Autodesk Fusion 360 part; units mm, degrees
(part 15 of 28)
sketch "Blinking Light House-PTH-drl_map (1)" plane through (0, 0, 1.4859) normal (0, 0, 1) x (1, 0, 0)
  line L0 (146.05, 0) -> (146.05, -5.08)
  line L1 (146.05, 0) -> (140.97, 0)
  line L2 (146.05, 0) -> (153.67, 0)
  line L3 (146.05, 0) -> (146.05, 6.985)
  line L4 (269.875, 36.83) -> (273.05, 36.83)
  line L5 (273.05, 36.83) -> (273.05, 5.08)
  line L6 (215.265, 36.83) -> (273.05, 36.83)
  line L7 (273.05, 5.08) -> (215.265, 5.08)
  line L8 (215.265, 5.08) -> (215.265, 36.83)
  line L9 (208.915, 36.83) -> (212.09, 36.83)
  line L10 (212.09, 36.83) -> (212.09, 5.08)
  line L11 (154.305, 36.83) -> (212.09, 36.83)
  line L12 (154.305, 5.08) -> (154.305, 36.83)
  line L13 (212.09, 5.08) -> (154.305, 5.08)
  line L14 (259.08, 97.79) -> (290.83, 97.79)
  line L15 (259.08, 40.005) -> (259.08, 97.79)
  line L16 (290.83, 97.79) -> (290.83, 40.005)
  line L17 (290.83, 40.005) -> (259.08, 40.005)
  line L18 (255.905, 97.79) -> (255.905, 40.005)
  line L19 (224.155, 97.79) -> (255.905, 97.79)
  line L20 (255.905, 40.005) -> (224.155, 40.005)
  line L21 (224.155, 40.005) -> (224.155, 97.79)
  line L22 (189.23, 97.79) -> (220.98, 97.79)
  line L23 (220.98, 97.79) -> (220.98, 40.005)
  line L24 (220.98, 40.005) -> (189.23, 40.005)
  line L25 (186.055, 40.005) -> (154.305, 40.005)
  line L26 (189.23, 40.005) -> (189.23, 97.79)
  line L27 (186.055, 97.79) -> (189.23, 97.79)
  line L28 (154.305, 40.005) -> (154.305, 97.79)
  line L29 (186.055, 40.005) -> (154.305, 40.005)
  line L30 (186.055, 97.79) -> (186.055, 40.005)
  line L31 (154.305, 97.79) -> (186.055, 97.79)
  line L32 (159.0815, 75.2735) -> (159.8315, 74.5235)
  line L33 (159.8315, 75.2735) -> (159.0815, 74.5235)
  line L34 (161.8515, 75.2735) -> (162.6015, 74.5235)
  line L35 (162.6015, 75.2735) -> (161.8515, 74.5235)
  line L36 (164.5815, 75.2735) -> (165.3315, 74.5235)
  line L37 (165.3315, 75.2735) -> (164.5815, 74.5235)
  line L38 (169.6166, 75.2153) -> (170.3666, 74.4653)
  line L39 (170.3666, 75.2153) -> (169.6166, 74.4653)
  line L40 (172.3866, 75.2153) -> (173.1366, 74.4653)
  line L41 (173.1366, 75.2153) -> (172.3866, 74.4653)
  line L42 (175.1166, 75.2153) -> (175.8666, 74.4653)
  line L43 (175.8666, 75.2153) -> (175.1166, 74.4653)
  line L44 (188.7653, 21.5184) -> (189.5153, 20.7684)
  line L45 (189.5153, 21.5184) -> (188.7653, 20.7684)
  line L46 (188.7653, 18.7484) -> (189.5153, 17.9984)
  line L47 (189.5153, 18.7484) -> (188.7653, 17.9984)
  line L48 (188.7653, 16.0184) -> (189.5153, 15.2684)
  line L49 (189.5153, 16.0184) -> (188.7653, 15.2684)
  line L50 (188.8235, 32.0535) -> (189.5735, 31.3035)
  line L51 (189.5735, 32.0535) -> (188.8235, 31.3035)
  line L52 (188.8235, 29.2835) -> (189.5735, 28.5335)
  line L53 (189.5735, 29.2835) -> (188.8235, 28.5335)
  line L54 (188.8235, 26.5535) -> (189.5735, 25.8035)
  line L55 (189.5735, 26.5535) -> (188.8235, 25.8035)
  line L56 (194.0065, 75.2735) -> (194.7565, 74.5235)
  line L57 (194.7565, 75.2735) -> (194.0065, 74.5235)
  line L58 (196.7765, 75.2735) -> (197.5265, 74.5235)
  line L59 (197.5265, 75.2735) -> (196.7765, 74.5235)
  line L60 (199.5065, 75.2735) -> (200.2565, 74.5235)
  line L61 (200.2565, 75.2735) -> (199.5065, 74.5235)
  line L62 (204.5416, 75.2153) -> (205.2916, 74.4653)
  line L63 (205.2916, 75.2153) -> (204.5416, 74.4653)
  line L64 (207.3116, 75.2153) -> (208.0616, 74.4653)
  line L65 (208.0616, 75.2153) -> (207.3116, 74.4653)
  line L66 (210.0416, 75.2153) -> (210.7916, 74.4653)
  line L67 (210.7916, 75.2153) -> (210.0416, 74.4653)
  line L68 (228.9315, 75.2735) -> (229.6815, 74.5235)
  line L69 (229.6815, 75.2735) -> (228.9315, 74.5235)
  line L70 (231.7015, 75.2735) -> (232.4515, 74.5235)
  line L71 (232.4515, 75.2735) -> (231.7015, 74.5235)
  line L72 (234.4315, 75.2735) -> (235.1815, 74.5235)
  line L73 (235.1815, 75.2735) -> (234.4315, 74.5235)
  line L74 (239.4666, 75.2153) -> (240.2166, 74.4653)
  line L75 (240.2166, 75.2153) -> (239.4666, 74.4653)
  line L76 (242.2366, 75.2153) -> (242.9866, 74.4653)
  line L77 (242.9866, 75.2153) -> (242.2366, 74.4653)
  line L78 (244.9666, 75.2153) -> (245.7166, 74.4653)
  line L79 (245.7166, 75.2153) -> (244.9666, 74.4653)
  line L80 (249.7253, 21.5184) -> (250.4753, 20.7684)
  line L81 (250.4753, 21.5184) -> (249.7253, 20.7684)
  line L82 (249.7253, 18.7484) -> (250.4753, 17.9984)
  line L83 (250.4753, 18.7484) -> (249.7253, 17.9984)
  line L84 (249.7253, 16.0184) -> (250.4753, 15.2684)
  line L85 (250.4753, 16.0184) -> (249.7253, 15.2684)
  line L86 (249.7835, 32.0535) -> (250.5335, 31.3035)
  line L87 (250.5335, 32.0535) -> (249.7835, 31.3035)
  line L88 (249.7835, 29.2835) -> (250.5335, 28.5335)
  line L89 (250.5335, 29.2835) -> (249.7835, 28.5335)
  line L90 (249.7835, 26.5535) -> (250.5335, 25.8035)
  line L91 (250.5335, 26.5535) -> (249.7835, 25.8035)
  line L92 (263.8565, 75.2735) -> (264.6065, 74.5235)
  line L93 (264.6065, 75.2735) -> (263.8565, 74.5235)
  line L94 (266.6265, 75.2735) -> (267.3765, 74.5235)
  line L95 (267.3765, 75.2735) -> (266.6265, 74.5235)
  line L96 (269.3565, 75.2735) -> (270.1065, 74.5235)
  line L97 (270.1065, 75.2735) -> (269.3565, 74.5235)
  line L98 (274.3916, 75.2153) -> (275.1416, 74.4653)
  line L99 (275.1416, 75.2153) -> (274.3916, 74.4653)
  line L100 (277.1616, 75.2153) -> (277.9116, 74.4653)
  line L101 (277.9116, 75.2153) -> (277.1616, 74.4653)
  line L102 (279.8916, 75.2153) -> (280.6416, 74.4653)
  line L103 (280.6416, 75.2153) -> (279.8916, 74.4653)
  circle A0 centre (159.6797, 53.7531) radius 0.4
  circle A1 centre (160.1942, 81.592) radius 0.4
  circle A2 centre (162.1797, 53.7531) radius 0.4
  circle A3 centre (162.2379, 64.1718) radius 0.4
  circle A4 centre (167.64, 20.28) radius 0.4
  circle A5 centre (167.64, 17.78) radius 0.4
  circle A6 centre (167.8142, 81.592) radius 0.4
  circle A7 centre (168.0531, 31.4553) radius 0.4
  circle A8 centre (168.0531, 28.9553) radius 0.4
  circle A9 centre (169.8579, 64.1718) radius 0.4
  circle A10 centre (170.855, 53.34) radius 0.4
  circle A11 centre (173.355, 53.34) radius 0.4
  circle A12 centre (175.3917, 12.367) radius 0.4
  circle A13 centre (178.4718, 28.8971) radius 0.4
  circle A14 centre (178.4718, 21.2771) radius 0.4
  circle A15 centre (178.768, 68.7117) radius 0.4
  circle A16 centre (178.768, 61.0917) radius 0.4
  circle A17 centre (179.6177, 92.0575) radius 0.4
  circle A18 centre (179.6177, 84.4375) radius 0.4
  circle A19 centre (183.0117, 12.367) radius 0.4
  circle A20 centre (194.6047, 53.7531) radius 0.4
  circle A21 centre (195.1192, 81.592) radius 0.4
  circle A22 centre (195.892, 30.9408) radius 0.4
  circle A23 centre (195.892, 23.3208) radius 0.4
  circle A24 centre (197.1047, 53.7531) radius 0.4
  circle A25 centre (197.1629, 64.1718) radius 0.4
  circle A26 centre (198.7375, 11.5173) radius 0.4
  circle A27 centre (202.7392, 81.592) radius 0.4
  circle A28 centre (204.7829, 64.1718) radius 0.4
  circle A29 centre (205.78, 53.34) radius 0.4
  circle A30 centre (206.3575, 11.5173) radius 0.4
  circle A31 centre (208.28, 53.34) radius 0.4
  circle A32 centre (213.693, 68.7117) radius 0.4
  circle A33 centre (213.693, 61.0917) radius 0.4
  circle A34 centre (214.5427, 92.0575) radius 0.4
  circle A35 centre (214.5427, 84.4375) radius 0.4
  circle A36 centre (228.6, 20.28) radius 0.4
  circle A37 centre (228.6, 17.78) radius 0.4
  circle A38 centre (229.0131, 31.4553) radius 0.4
  circle A39 centre (229.0131, 28.9553) radius 0.4
  circle A40 centre (229.5297, 53.7531) radius 0.4
  circle A41 centre (230.0442, 81.592) radius 0.4
  circle A42 centre (232.0297, 53.7531) radius 0.4
  circle A43 centre (232.0879, 64.1718) radius 0.4
  circle A44 centre (236.3517, 12.367) radius 0.4
  circle A45 centre (237.6642, 81.592) radius 0.4
  circle A46 centre (239.4318, 28.8971) radius 0.4
  circle A47 centre (239.4318, 21.2771) radius 0.4
  circle A48 centre (239.7079, 64.1718) radius 0.4
  circle A49 centre (240.705, 53.34) radius 0.4
  circle A50 centre (243.205, 53.34) radius 0.4
  circle A51 centre (243.9717, 12.367) radius 0.4
  circle A52 centre (248.618, 68.7117) radius 0.4
  circle A53 centre (248.618, 61.0917) radius 0.4
  circle A54 centre (249.4677, 92.0575) radius 0.4
  circle A55 centre (249.4677, 84.4375) radius 0.4
  circle A56 centre (256.852, 30.9408) radius 0.4
  circle A57 centre (256.852, 23.3208) radius 0.4
  circle A58 centre (259.6975, 11.5173) radius 0.4
  circle A59 centre (264.4547, 53.7531) radius 0.4
  circle A60 centre (264.9692, 81.592) radius 0.4
  circle A61 centre (266.9547, 53.7531) radius 0.4
  circle A62 centre (267.0129, 64.1718) radius 0.4
  circle A63 centre (267.3175, 11.5173) radius 0.4
  circle A64 centre (272.5892, 81.592) radius 0.4
  circle A65 centre (274.6329, 64.1718) radius 0.4
  circle A66 centre (275.63, 53.34) radius 0.4
  circle A67 centre (278.13, 53.34) radius 0.4
  circle A68 centre (283.543, 68.7117) radius 0.4
  circle A69 centre (283.543, 61.0917) radius 0.4
  circle A70 centre (284.3927, 92.0575) radius 0.4
  circle A71 centre (284.3927, 84.4375) radius 0.4
  line L104 (167.0374, 91.0233) -> (167.0374, 90.1233)
  line L105 (166.5874, 90.5733) -> (167.4874, 90.5733)
  line L106 (169.5774, 91.0233) -> (169.5774, 90.1233)
  line L107 (169.1274, 90.5733) -> (170.0274, 90.5733)
  line L108 (201.9624, 91.0233) -> (201.9624, 90.1233)
  line L109 (201.5124, 90.5733) -> (202.4124, 90.5733)
  line L110 (204.5024, 91.0233) -> (204.5024, 90.1233)
  line L111 (204.0524, 90.5733) -> (204.9524, 90.5733)
  line L112 (204.8733, 24.5476) -> (204.8733, 23.6476)
  line L113 (204.4233, 24.0976) -> (205.3233, 24.0976)
  line L114 (204.8733, 22.0076) -> (204.8733, 21.1076)
  line L115 (204.4233, 21.5576) -> (205.3233, 21.5576)
  line L116 (236.8874, 91.0233) -> (236.8874, 90.1233)
  line L117 (236.4374, 90.5733) -> (237.3374, 90.5733)
  line L118 (239.4274, 91.0233) -> (239.4274, 90.1233)
  line L119 (238.9774, 90.5733) -> (239.8774, 90.5733)
  line L120 (265.8333, 24.5476) -> (265.8333, 23.6476)
  line L121 (265.3833, 24.0976) -> (266.2833, 24.0976)
  line L122 (265.8333, 22.0076) -> (265.8333, 21.1076)
  line L123 (265.3833, 21.5576) -> (266.2833, 21.5576)
  line L124 (271.8124, 91.0233) -> (271.8124, 90.1233)
  line L125 (271.3624, 90.5733) -> (272.2624, 90.5733)
  line L126 (274.3524, 91.0233) -> (274.3524, 90.1233)
  line L127 (273.9024, 90.5733) -> (274.8024, 90.5733)
  line L128 (156.9524, 31.2056) -> (156.9524, 31.9128)
  line L129 (156.9524, 31.9128) -> (156.2453, 31.9128)
  line L130 (156.2453, 31.9128) -> (156.2453, 31.2056)
  line L131 (156.2453, 31.2056) -> (156.9524, 31.2056)
  line L132 (156.9524, 28.6656) -> (156.9524, 29.3728)
  line L133 (156.9524, 29.3728) -> (156.2453, 29.3728)
  line L134 (156.2453, 29.3728) -> (156.2453, 28.6656)
  line L135 (156.2453, 28.6656) -> (156.9524, 28.6656)
  line L136 (159.9294, 41.9453) -> (159.9294, 42.6524)
  line L137 (159.9294, 42.6524) -> (159.2222, 42.6524)
  line L138 (159.2222, 42.6524) -> (159.2222, 41.9453)
  line L139 (159.2222, 41.9453) -> (159.9294, 41.9453)
  line L140 (162.4694, 41.9453) -> (162.4694, 42.6524)
  line L141 (162.4694, 42.6524) -> (161.7622, 42.6524)
  line L142 (161.7622, 42.6524) -> (161.7622, 41.9453)
  line L143 (161.7622, 41.9453) -> (162.4694, 41.9453)
  line L144 (194.8544, 41.9453) -> (194.8544, 42.6524)
  line L145 (194.8544, 42.6524) -> (194.1472, 42.6524)
  line L146 (194.1472, 42.6524) -> (194.1472, 41.9453)
  line L147 (194.1472, 41.9453) -> (194.8544, 41.9453)
  line L148 (197.3944, 41.9453) -> (197.3944, 42.6524)
  line L149 (197.3944, 42.6524) -> (196.6872, 42.6524)
  line L150 (196.6872, 42.6524) -> (196.6872, 41.9453)
  line L151 (196.6872, 41.9453) -> (197.3944, 41.9453)
  line L152 (217.9124, 31.2056) -> (217.9124, 31.9128)
  line L153 (217.9124, 31.9128) -> (217.2053, 31.9128)
  line L154 (217.2053, 31.9128) -> (217.2053, 31.2056)
  line L155 (217.2053, 31.2056) -> (217.9124, 31.2056)
  line L156 (217.9124, 28.6656) -> (217.9124, 29.3728)
  line L157 (217.9124, 29.3728) -> (217.2053, 29.3728)
  line L158 (217.2053, 29.3728) -> (217.2053, 28.6656)
  line L159 (217.2053, 28.6656) -> (217.9124, 28.6656)
  line L160 (229.7794, 41.9453) -> (229.7794, 42.6524)
  line L161 (229.7794, 42.6524) -> (229.0722, 42.6524)
  line L162 (229.0722, 42.6524) -> (229.0722, 41.9453)
  line L163 (229.0722, 41.9453) -> (229.7794, 41.9453)
  line L164 (232.3194, 41.9453) -> (232.3194, 42.6524)
  line L165 (232.3194, 42.6524) -> (231.6122, 42.6524)
  line L166 (231.6122, 42.6524) -> (231.6122, 41.9453)
  line L167 (231.6122, 41.9453) -> (232.3194, 41.9453)
  line L168 (264.7044, 41.9453) -> (264.7044, 42.6524)
  line L169 (264.7044, 42.6524) -> (263.9972, 42.6524)
  line L170 (263.9972, 42.6524) -> (263.9972, 41.9453)
  line L171 (263.9972, 41.9453) -> (264.7044, 41.9453)
  line L172 (267.2444, 41.9453) -> (267.2444, 42.6524)
  line L173 (267.2444, 42.6524) -> (266.5372, 42.6524)
  line L174 (266.5372, 42.6524) -> (266.5372, 41.9453)
  line L175 (266.5372, 41.9453) -> (267.2444, 41.9453)
  line L176 (143.5528, -8.2198) -> (143.5528, -6.2198)
  line L177 (143.5528, -6.2198) -> (144.029, -6.2198)
  line L178 (144.029, -6.2198) -> (144.3147, -6.3151)
  line L179 (144.3147, -6.3151) -> (144.5051, -6.5056)
  line L180 (144.5051, -6.5056) -> (144.6004, -6.696)
  line L181 (144.6004, -6.696) -> (144.6956, -7.077)
  line L182 (144.6956, -7.077) -> (144.6956, -7.3627)
  line L183 (144.6956, -7.3627) -> (144.6004, -7.7436)
  line L184 (144.6004, -7.7436) -> (144.5051, -7.9341)
  line L185 (144.5051, -7.9341) -> (144.3147, -8.1246)
  line L186 (144.3147, -8.1246) -> (144.029, -8.2198)
  line L187 (144.029, -8.2198) -> (143.5528, -8.2198)
  line L188 (145.5528, -8.2198) -> (145.5528, -6.8865)
  line L189 (145.5528, -7.2675) -> (145.648, -7.077)
  line L190 (145.648, -7.077) -> (145.7432, -6.9817)
  line L191 (145.7432, -6.9817) -> (145.9337, -6.8865)
  line L192 (145.9337, -6.8865) -> (146.1242, -6.8865)
  line L193 (146.7909, -8.2198) -> (146.7909, -6.8865)
  line L194 (146.7909, -6.2198) -> (146.6956, -6.3151)
  line L195 (146.6956, -6.3151) -> (146.7909, -6.4103)
  line L196 (146.7909, -6.4103) -> (146.8861, -6.3151)
  line L197 (146.8861, -6.3151) -> (146.7909, -6.2198)
  line L198 (146.7909, -6.2198) -> (146.7909, -6.4103)
  line L199 (148.029, -8.2198) -> (147.8385, -8.1246)
  line L200 (147.8385, -8.1246) -> (147.7432, -7.9341)
  line L201 (147.7432, -7.9341) -> (147.7432, -6.2198)
  line L202 (149.0766, -8.2198) -> (148.8861, -8.1246)
  line L203 (148.8861, -8.1246) -> (148.7909, -7.9341)
  line L204 (148.7909, -7.9341) -> (148.7909, -6.2198)
  line L205 (151.3623, -8.2198) -> (151.3623, -6.2198)
  line L206 (151.3623, -6.2198) -> (152.029, -7.6484)
  line L207 (152.029, -7.6484) -> (152.6956, -6.2198)
  line L208 (152.6956, -6.2198) -> (152.6956, -8.2198)
  line L209 (154.5051, -8.2198) -> (154.5051, -7.1722)
  line L210 (154.5051, -7.1722) -> (154.4099, -6.9817)
  line L211 (154.4099, -6.9817) -> (154.2194, -6.8865)
  line L212 (154.2194, -6.8865) -> (153.8385, -6.8865)
  line L213 (153.8385, -6.8865) -> (153.648, -6.9817)
  line L214 (154.5051, -8.1246) -> (154.3147, -8.2198)
  line L215 (154.3147, -8.2198) -> (153.8385, -8.2198)
  line L216 (153.8385, -8.2198) -> (153.648, -8.1246)
  line L217 (153.648, -8.1246) -> (153.5528, -7.9341)
  line L218 (153.5528, -7.9341) -> (153.5528, -7.7436)
  line L219 (153.5528, -7.7436) -> (153.648, -7.5532)
  line L220 (153.648, -7.5532) -> (153.8385, -7.4579)
  line L221 (153.8385, -7.4579) -> (154.3147, -7.4579)
  line L222 (154.3147, -7.4579) -> (154.5051, -7.3627)
  line L223 (155.4575, -6.8865) -> (155.4575, -8.8865)
  line L224 (155.4575, -6.9817) -> (155.648, -6.8865)
  line L225 (155.648, -6.8865) -> (156.029, -6.8865)
  line L226 (156.029, -6.8865) -> (156.2194, -6.9817)
  line L227 (156.2194, -6.9817) -> (156.3147, -7.077)
  line L228 (156.3147, -7.077) -> (156.4099, -7.2675)
  line L229 (156.4099, -7.2675) -> (156.4099, -7.8389)
  line L230 (156.4099, -7.8389) -> (156.3147, -8.0294)
  line L231 (156.3147, -8.0294) -> (156.2194, -8.1246)
  line L232 (156.2194, -8.1246) -> (156.029, -8.2198)
  line L233 (156.029, -8.2198) -> (155.648, -8.2198)
  line L234 (155.648, -8.2198) -> (155.4575, -8.1246)
  line L235 (157.2671, -8.0294) -> (157.3623, -8.1246)
  line L236 (157.3623, -8.1246) -> (157.2671, -8.2198)
  line L237 (157.2671, -8.2198) -> (157.1718, -8.1246)
  line L238 (157.1718, -8.1246) -> (157.2671, -8.0294)
  line L239 (157.2671, -8.0294) -> (157.2671, -8.2198)
  line L240 (157.2671, -6.9817) -> (157.3623, -7.077)
  line L241 (157.3623, -7.077) -> (157.2671, -7.1722)
  line L242 (157.2671, -7.1722) -> (157.1718, -7.077)
  line L243 (157.1718, -7.077) -> (157.2671, -6.9817)
  line L244 (157.2671, -6.9817) -> (157.2671, -7.1722)
  line L245 (140.195, -11.13) -> (140.945, -11.88)
  line L246 (140.945, -11.13) -> (140.195, -11.88)
  line L247 (143.9337, -10.4198) -> (144.1242, -10.4198)
  line L248 (144.1242, -10.4198) -> (144.3147, -10.5151)
  line L249 (144.3147, -10.5151) -> (144.4099, -10.6103)
  line L250 (144.4099, -10.6103) -> (144.5051, -10.8008)
  line L251 (144.5051, -10.8008) -> (144.6004, -11.1817)
  line L252 (144.6004, -11.1817) -> (144.6004, -11.6579)
  line L253 (144.6004, -11.6579) -> (144.5051, -12.0389)
  line L254 (144.5051, -12.0389) -> (144.4099, -12.2294)
  line L255 (144.4099, -12.2294) -> (144.3147, -12.3246)
  line L256 (144.3147, -12.3246) -> (144.1242, -12.4198)
  line L257 (144.1242, -12.4198) -> (143.9337, -12.4198)
  line L258 (143.9337, -12.4198) -> (143.7432, -12.3246)
  line L259 (143.7432, -12.3246) -> (143.648, -12.2294)
  line L260 (143.648, -12.2294) -> (143.5528, -12.0389)
  line L261 (143.5528, -12.0389) -> (143.4575, -11.6579)
  line L262 (143.4575, -11.6579) -> (143.4575, -11.1817)
  line L263 (143.4575, -11.1817) -> (143.5528, -10.8008)
  line L264 (143.5528, -10.8008) -> (143.648, -10.6103)
  line L265 (143.648, -10.6103) -> (143.7432, -10.5151)
  line L266 (143.7432, -10.5151) -> (143.9337, -10.4198)
  line L267 (145.4575, -12.2294) -> (145.5528, -12.3246)
  line L268 (145.5528, -12.3246) -> (145.4575, -12.4198)
  line L269 (145.4575, -12.4198) -> (145.3623, -12.3246)
  line L270 (145.3623, -12.3246) -> (145.4575, -12.2294)
  line L271 (145.4575, -12.2294) -> (145.4575, -12.4198)
  line L272 (146.2194, -10.4198) -> (147.5528, -10.4198)
  line L273 (147.5528, -10.4198) -> (146.6956, -12.4198)
  line L274 (149.2671, -10.4198) -> (148.3147, -10.4198)
  line L275 (148.3147, -10.4198) -> (148.2194, -11.3722)
  line L276 (148.2194, -11.3722) -> (148.3147, -11.277)
  line L277 (148.3147, -11.277) -> (148.5051, -11.1817)
  line L278 (148.5051, -11.1817) -> (148.9813, -11.1817)
  line L279 (148.9813, -11.1817) -> (149.1718, -11.277)
  line L280 (149.1718, -11.277) -> (149.2671, -11.3722)
  line L281 (149.2671, -11.3722) -> (149.3623, -11.5627)
  line L282 (149.3623, -11.5627) -> (149.3623, -12.0389)
  line L283 (149.3623, -12.0389) -> (149.2671, -12.2294)
  line L284 (149.2671, -12.2294) -> (149.1718, -12.3246)
  line L285 (149.1718, -12.3246) -> (148.9813, -12.4198)
  line L286 (148.9813, -12.4198) -> (148.5051, -12.4198)
  line L287 (148.5051, -12.4198) -> (148.3147, -12.3246)
  line L288 (148.3147, -12.3246) -> (148.2194, -12.2294)
  line L289 (150.6004, -10.4198) -> (150.7909, -10.4198)
  line L290 (150.7909, -10.4198) -> (150.9813, -10.5151)
  line L291 (150.9813, -10.5151) -> (151.0766, -10.6103)
  line L292 (151.0766, -10.6103) -> (151.1718, -10.8008)
  line L293 (151.1718, -10.8008) -> (151.2671, -11.1817)
  line L294 (151.2671, -11.1817) -> (151.2671, -11.6579)
  line L295 (151.2671, -11.6579) -> (151.1718, -12.0389)
  line L296 (151.1718, -12.0389) -> (151.0766, -12.2294)
  line L297 (151.0766, -12.2294) -> (150.9813, -12.3246)
  line L298 (150.9813, -12.3246) -> (150.7909, -12.4198)
  line L299 (150.7909, -12.4198) -> (150.6004, -12.4198)
  line L300 (150.6004, -12.4198) -> (150.4099, -12.3246)
  line L301 (150.4099, -12.3246) -> (150.3147, -12.2294)
  line L302 (150.3147, -12.2294) -> (150.2194, -12.0389)
  line L303 (150.2194, -12.0389) -> (150.1242, -11.6579)
  line L304 (150.1242, -11.6579) -> (150.1242, -11.1817)
  line L305 (150.1242, -11.1817) -> (150.2194, -10.8008)
  line L306 (150.2194, -10.8008) -> (150.3147, -10.6103)
  line L307 (150.3147, -10.6103) -> (150.4099, -10.5151)
  line L308 (150.4099, -10.5151) -> (150.6004, -10.4198)
  line L309 (152.1242, -12.4198) -> (152.1242, -11.0865)
  line L310 (152.1242, -11.277) -> (152.2194, -11.1817)
  line L311 (152.2194, -11.1817) -> (152.4099, -11.0865)
  line L312 (152.4099, -11.0865) -> (152.6956, -11.0865)
  line L313 (152.6956, -11.0865) -> (152.8861, -11.1817)
  line L314 (152.8861, -11.1817) -> (152.9813, -11.3722)
  line L315 (152.9813, -11.3722) -> (152.9813, -12.4198)
  line L316 (152.9813, -11.3722) -> (153.0766, -11.1817)
  line L317 (153.0766, -11.1817) -> (153.2671, -11.0865)
  line L318 (153.2671, -11.0865) -> (153.5528, -11.0865)
  line L319 (153.5528, -11.0865) -> (153.7432, -11.1817)
  line L320 (153.7432, -11.1817) -> (153.8385, -11.3722)
  line L321 (153.8385, -11.3722) -> (153.8385, -12.4198)
  line L322 (154.7909, -12.4198) -> (154.7909, -11.0865)
  line L323 (154.7909, -11.277) -> (154.8861, -11.1817)
  line L324 (154.8861, -11.1817) -> (155.0766, -11.0865)
  line L325 (155.0766, -11.0865) -> (155.3623, -11.0865)
  line L326 (155.3623, -11.0865) -> (155.5528, -11.1817)
  line L327 (155.5528, -11.1817) -> (155.648, -11.3722)
  line L328 (155.648, -11.3722) -> (155.648, -12.4198)
  line L329 (155.648, -11.3722) -> (155.7432, -11.1817)
  line L330 (155.7432, -11.1817) -> (155.9337, -11.0865)
  line L331 (155.9337, -11.0865) -> (156.2194, -11.0865)
  line L332 (156.2194, -11.0865) -> (156.4099, -11.1817)
  line L333 (156.4099, -11.1817) -> (156.5051, -11.3722)
  line L334 (156.5052, -11.3722) -> (156.5052, -12.4198)
  line L335 (160.4099, -10.3246) -> (158.6956, -12.896)
  line L336 (162.9813, -10.4198) -> (163.1718, -10.4198)
  line L337 (163.1718, -10.4198) -> (163.3623, -10.5151)
  line L338 (163.3623, -10.5151) -> (163.4575, -10.6103)
  line L339 (163.4575, -10.6103) -> (163.5528, -10.8008)
  line L340 (163.5528, -10.8008) -> (163.648, -11.1817)
  line L341 (163.648, -11.1817) -> (163.648, -11.6579)
  line L342 (163.648, -11.6579) -> (163.5528, -12.0389)
  line L343 (163.5528, -12.0389) -> (163.4575, -12.2294)
  line L344 (163.4575, -12.2294) -> (163.3623, -12.3246)
  line L345 (163.3623, -12.3246) -> (163.1718, -12.4198)
  line L346 (163.1718, -12.4198) -> (162.9813, -12.4198)
  line L347 (162.9813, -12.4198) -> (162.7909, -12.3246)
  line L348 (162.7909, -12.3246) -> (162.6956, -12.2294)
  line L349 (162.6956, -12.2294) -> (162.6004, -12.0389)
  line L350 (162.6004, -12.0389) -> (162.5052, -11.6579)
  line L351 (162.5052, -11.6579) -> (162.5052, -11.1817)
  line L352 (162.5052, -11.1817) -> (162.6004, -10.8008)
  line L353 (162.6004, -10.8008) -> (162.6956, -10.6103)
  line L354 (162.6956, -10.6103) -> (162.7909, -10.5151)
  line L355 (162.7909, -10.5151) -> (162.9813, -10.4198)
  line L356 (164.5052, -12.2294) -> (164.6004, -12.3246)
  line L357 (164.6004, -12.3246) -> (164.5052, -12.4198)
  line L358 (164.5052, -12.4198) -> (164.4099, -12.3246)
  line L359 (164.4099, -12.3246) -> (164.5052, -12.2294)
  line L360 (164.5052, -12.2294) -> (164.5052, -12.4198)
  line L361 (165.8385, -10.4198) -> (166.029, -10.4198)
  line L362 (166.029, -10.4198) -> (166.2194, -10.5151)
  line L363 (166.2194, -10.5151) -> (166.3147, -10.6103)
  line L364 (166.3147, -10.6103) -> (166.4099, -10.8008)
  line L365 (166.4099, -10.8008) -> (166.5052, -11.1817)
  line L366 (166.5052, -11.1817) -> (166.5052, -11.6579)
  line L367 (166.5052, -11.6579) -> (166.4099, -12.0389)
  line L368 (166.4099, -12.0389) -> (166.3147, -12.2294)
  line L369 (166.3147, -12.2294) -> (166.2194, -12.3246)
  line L370 (166.2194, -12.3246) -> (166.029, -12.4198)
  line L371 (166.029, -12.4198) -> (165.8385, -12.4198)
  line L372 (165.8385, -12.4198) -> (165.648, -12.3246)
  line L373 (165.648, -12.3246) -> (165.5528, -12.2294)
  line L374 (165.5528, -12.2294) -> (165.4575, -12.0389)
  line L375 (165.4575, -12.0389) -> (165.3623, -11.6579)
  line L376 (165.3623, -11.6579) -> (165.3623, -11.1817)
  line L377 (165.3623, -11.1817) -> (165.4575, -10.8008)
  line L378 (165.4575, -10.8008) -> (165.5528, -10.6103)
  line L379 (165.5528, -10.6103) -> (165.648, -10.5151)
  line L380 (165.648, -10.5151) -> (165.8385, -10.4198)
  line L381 (167.2671, -10.6103) -> (167.3623, -10.5151)
  line L382 (167.3623, -10.5151) -> (167.5528, -10.4198)
  line L383 (167.5528, -10.4198) -> (168.029, -10.4198)
  line L384 (168.029, -10.4198) -> (168.2194, -10.5151)
  line L385 (168.2194, -10.5151) -> (168.3147, -10.6103)
  line L386 (168.3147, -10.6103) -> (168.4099, -10.8008)
  line L387 (168.4099, -10.8008) -> (168.4099, -10.9913)
  line L388 (168.4099, -10.9913) -> (168.3147, -11.277)
  line L389 (168.3147, -11.277) -> (167.1718, -12.4198)
  line L390 (167.1718, -12.4198) -> (168.4099, -12.4198)
  line L391 (169.3623, -12.4198) -> (169.7432, -12.4198)
  line L392 (169.7432, -12.4198) -> (169.9337, -12.3246)
  line L393 (169.9337, -12.3246) -> (170.029, -12.2294)
  line L394 (170.029, -12.2294) -> (170.2194, -11.9436)
  line L395 (170.2194, -11.9436) -> (170.3147, -11.5627)
  line L396 (170.3147, -11.5627) -> (170.3147, -10.8008)
  line L397 (170.3147, -10.8008) -> (170.2194, -10.6103)
  line L398 (170.2194, -10.6103) -> (170.1242, -10.5151)
  line L399 (170.1242, -10.5151) -> (169.9337, -10.4198)
  line L400 (169.9337, -10.4198) -> (169.5528, -10.4198)
  line L401 (169.5528, -10.4198) -> (169.3623, -10.5151)
  line L402 (169.3623, -10.5151) -> (169.2671, -10.6103)
  line L403 (169.2671, -10.6103) -> (169.1718, -10.8008)
  line L404 (169.1718, -10.8008) -> (169.1718, -11.277)
  line L405 (169.1718, -11.277) -> (169.2671, -11.4675)
  line L406 (169.2671, -11.4675) -> (169.3623, -11.5627)
  line L407 (169.3623, -11.5627) -> (169.5528, -11.6579)
  line L408 (169.5528, -11.6579) -> (169.9337, -11.6579)
  line L409 (169.9337, -11.6579) -> (170.1242, -11.5627)
  line L410 (170.1242, -11.5627) -> (170.2194, -11.4675)
  line L411 (170.2194, -11.4675) -> (170.3147, -11.277)
  line L412 (172.1242, -10.4198) -> (171.1718, -10.4198)
  line L413 (171.1718, -10.4198) -> (171.0766, -11.3722)
  line L414 (171.0766, -11.3722) -> (171.1718, -11.277)
  line L415 (171.1718, -11.277) -> (171.3623, -11.1817)
  line L416 (171.3623, -11.1817) -> (171.8385, -11.1817)
  line L417 (171.8385, -11.1817) -> (172.029, -11.277)
  line L418 (172.029, -11.277) -> (172.1242, -11.3722)
  line L419 (172.1242, -11.3722) -> (172.2194, -11.5627)
  line L420 (172.2194, -11.5627) -> (172.2194, -12.0389)
  line L421 (172.2194, -12.0389) -> (172.1242, -12.2294)
  line L422 (172.1242, -12.2294) -> (172.029, -12.3246)
  line L423 (172.029, -12.3246) -> (171.8385, -12.4198)
  line L424 (171.8385, -12.4198) -> (171.3623, -12.4198)
  line L425 (171.3623, -12.4198) -> (171.1718, -12.3246)
  line L426 (171.1718, -12.3246) -> (171.0766, -12.2294)
  line L427 (172.9813, -10.4198) -> (172.9813, -10.8008)
  line L428 (173.7432, -10.4198) -> (173.7432, -10.8008)
  line L429 (176.6956, -13.1817) -> (176.6004, -13.0865)
  line L430 (176.6004, -13.0865) -> (176.4099, -12.8008)
  line L431 (176.4099, -12.8008) -> (176.3147, -12.6103)
  line L432 (176.3147, -12.6103) -> (176.2194, -12.3246)
  line L433 (176.2194, -12.3246) -> (176.1242, -11.8484)
  line L434 (176.1242, -11.8484) -> (176.1242, -11.4675)
  line L435 (176.1242, -11.4675) -> (176.2194, -10.9913)
  line L436 (176.2194, -10.9913) -> (176.3147, -10.7056)
  line L437 (176.3147, -10.7056) -> (176.4099, -10.5151)
  line L438 (176.4099, -10.5151) -> (176.6004, -10.2294)
  line L439 (176.6004, -10.2294) -> (176.6956, -10.1341)
  line L440 (177.2671, -10.4198) -> (178.5052, -10.4198)
  line L441 (178.5052, -10.4198) -> (177.8385, -11.1817)
  line L442 (177.8385, -11.1817) -> (178.1242, -11.1817)
  line L443 (178.1242, -11.1817) -> (178.3147, -11.277)
  line L444 (178.3147, -11.277) -> (178.4099, -11.3722)
  line L445 (178.4099, -11.3722) -> (178.5052, -11.5627)
  line L446 (178.5052, -11.5627) -> (178.5052, -12.0389)
  line L447 (178.5052, -12.0389) -> (178.4099, -12.2294)
  line L448 (178.4099, -12.2294) -> (178.3147, -12.3246)
  line L449 (178.3147, -12.3246) -> (178.1242, -12.4198)
  line L450 (178.1242, -12.4198) -> (177.5528, -12.4198)
  line L451 (177.5528, -12.4198) -> (177.3623, -12.3246)
  line L452 (177.3623, -12.3246) -> (177.2671, -12.2294)
  line L453 (180.2194, -10.4198) -> (179.8385, -10.4198)
  line L454 (179.8385, -10.4198) -> (179.648, -10.5151)
  line L455 (179.648, -10.5151) -> (179.5528, -10.6103)
  line L456 (179.5528, -10.6103) -> (179.3623, -10.896)
  line L457 (179.3623, -10.896) -> (179.2671, -11.277)
  line L458 (179.2671, -11.277) -> (179.2671, -12.0389)
  line L459 (179.2671, -12.0389) -> (179.3623, -12.2294)
  line L460 (179.3623, -12.2294) -> (179.4575, -12.3246)
  line L461 (179.4575, -12.3246) -> (179.648, -12.4198)
  line L462 (179.648, -12.4198) -> (180.029, -12.4198)
  line L463 (180.029, -12.4198) -> (180.2194, -12.3246)
  line L464 (180.2194, -12.3246) -> (180.3147, -12.2294)
  line L465 (180.3147, -12.2294) -> (180.4099, -12.0389)
  line L466 (180.4099, -12.0389) -> (180.4099, -11.5627)
  line L467 (180.4099, -11.5627) -> (180.3147, -11.3722)
  line L468 (180.3147, -11.3722) -> (180.2194, -11.277)
  line L469 (180.2194, -11.277) -> (180.029, -11.1817)
  line L470 (180.029, -11.1817) -> (179.648, -11.1817)
  line L471 (179.648, -11.1817) -> (179.4575, -11.277)
  line L472 (179.4575, -11.277) -> (179.3623, -11.3722)
  line L473 (179.3623, -11.3722) -> (179.2671, -11.5627)
  line L474 (182.7909, -12.4198) -> (182.7909, -10.4198)
  line L475 (183.648, -12.4198) -> (183.648, -11.3722)
  line L476 (183.648, -11.3722) -> (183.5528, -11.1817)
  line L477 (183.5528, -11.1817) -> (183.3623, -11.0865)
  line L478 (183.3623, -11.0865) -> (183.0766, -11.0865)
  line L479 (183.0766, -11.0865) -> (182.8861, -11.1817)
  line L480 (182.8861, -11.1817) -> (182.7909, -11.277)
  line L481 (184.8861, -12.4198) -> (184.6956, -12.3246)
  line L482 (184.6956, -12.3246) -> (184.6004, -12.2294)
  line L483 (184.6004, -12.2294) -> (184.5052, -12.0389)
  line L484 (184.5052, -12.0389) -> (184.5052, -11.4675)
  line L485 (184.5052, -11.4675) -> (184.6004, -11.277)
  line L486 (184.6004, -11.277) -> (184.6956, -11.1817)
  line L487 (184.6956, -11.1817) -> (184.8861, -11.0865)
  line L488 (184.8861, -11.0865) -> (185.1718, -11.0865)
  line L489 (185.1718, -11.0865) -> (185.3623, -11.1817)
  line L490 (185.3623, -11.1817) -> (185.4575, -11.277)
  line L491 (185.4575, -11.277) -> (185.5528, -11.4675)
  line L492 (185.5528, -11.4675) -> (185.5528, -12.0389)
  line L493 (185.5528, -12.0389) -> (185.4575, -12.2294)
  line L494 (185.4575, -12.2294) -> (185.3623, -12.3246)
  line L495 (185.3623, -12.3246) -> (185.1718, -12.4198)
  line L496 (185.1718, -12.4198) -> (184.8861, -12.4198)
  line L497 (186.6956, -12.4198) -> (186.5052, -12.3246)
  line L498 (186.5052, -12.3246) -> (186.4099, -12.1341)
  line L499 (186.4099, -12.1341) -> (186.4099, -10.4198)
  line L500 (188.2194, -12.3246) -> (188.029, -12.4198)
  line L501 (188.029, -12.4198) -> (187.648, -12.4198)
  line L502 (187.648, -12.4198) -> (187.4575, -12.3246)
  line L503 (187.4575, -12.3246) -> (187.3623, -12.1341)
  line L504 (187.3623, -12.1341) -> (187.3623, -11.3722)
  line L505 (187.3623, -11.3722) -> (187.4575, -11.1817)
  line L506 (187.4575, -11.1817) -> (187.648, -11.0865)
  line L507 (187.648, -11.0865) -> (188.029, -11.0865)
  line L508 (188.029, -11.0865) -> (188.2194, -11.1817)
  line L509 (188.2194, -11.1817) -> (188.3147, -11.3722)
  line L510 (188.3147, -11.3722) -> (188.3147, -11.5627)
  line L511 (188.3147, -11.5627) -> (187.3623, -11.7532)
  line L512 (189.0766, -12.3246) -> (189.2671, -12.4198)
  line L513 (189.2671, -12.4198) -> (189.648, -12.4198)
  line L514 (189.648, -12.4198) -> (189.8385, -12.3246)
  line L515 (189.8385, -12.3246) -> (189.9337, -12.1341)
  line L516 (189.9337, -12.1341) -> (189.9337, -12.0389)
  line L517 (189.9337, -12.0389) -> (189.8385, -11.8484)
  line L518 (189.8385, -11.8484) -> (189.648, -11.7532)
  line L519 (189.648, -11.7532) -> (189.3623, -11.7532)
  line L520 (189.3623, -11.7532) -> (189.1718, -11.6579)
  line L521 (189.1718, -11.6579) -> (189.0766, -11.4675)
  line L522 (189.0766, -11.4675) -> (189.0766, -11.3722)
  line L523 (189.0766, -11.3722) -> (189.1718, -11.1817)
  line L524 (189.1718, -11.1817) -> (189.3623, -11.0865)
  line L525 (189.3623, -11.0865) -> (189.648, -11.0865)
  line L526 (189.648, -11.0865) -> (189.8385, -11.1817)
  line L527 (190.6004, -13.1817) -> (190.6956, -13.0865)
  line L528 (190.6956, -13.0865) -> (190.8861, -12.8008)
  line L529 (190.8861, -12.8008) -> (190.9813, -12.6103)
  line L530 (190.9813, -12.6103) -> (191.0766, -12.3246)
  line L531 (191.0766, -12.3246) -> (191.1718, -11.8484)
  line L532 (191.1718, -11.8484) -> (191.1718, -11.4675)
  line L533 (191.1718, -11.4675) -> (191.0766, -10.9913)
  line L534 (191.0766, -10.9913) -> (190.9813, -10.7056)
  line L535 (190.9813, -10.7056) -> (190.8861, -10.5151)
  line L536 (190.8861, -10.5151) -> (190.6956, -10.2294)
  line L537 (190.6956, -10.2294) -> (190.6004, -10.1341)
  circle A72 centre (140.545, -14.145) radius 0.4
  line L538 (143.9337, -13.0598) -> (144.1242, -13.0598)
  line L539 (144.1242, -13.0598) -> (144.3147, -13.1551)
  line L540 (144.3147, -13.1551) -> (144.4099, -13.2503)
  line L541 (144.4099, -13.2503) -> (144.5051, -13.4408)
  line L542 (144.5051, -13.4408) -> (144.6004, -13.8217)
  line L543 (144.6004, -13.8217) -> (144.6004, -14.2979)
  line L544 (144.6004, -14.2979) -> (144.5051, -14.6789)
  line L545 (144.5051, -14.6789) -> (144.4099, -14.8694)
  line L546 (144.4099, -14.8694) -> (144.3147, -14.9646)
  line L547 (144.3147, -14.9646) -> (144.1242, -15.0598)
  line L548 (144.1242, -15.0598) -> (143.9337, -15.0598)
  line L549 (143.9337, -15.0598) -> (143.7432, -14.9646)
  line L550 (143.7432, -14.9646) -> (143.648, -14.8694)
  line L551 (143.648, -14.8694) -> (143.5528, -14.6789)
  line L552 (143.5528, -14.6789) -> (143.4575, -14.2979)
  line L553 (143.4575, -14.2979) -> (143.4575, -13.8217)
  line L554 (143.4575, -13.8217) -> (143.5528, -13.4408)
  line L555 (143.5528, -13.4408) -> (143.648, -13.2503)
  line L556 (143.648, -13.2503) -> (143.7432, -13.1551)
  line L557 (143.7432, -13.1551) -> (143.9337, -13.0598)
  line L558 (145.4575, -14.8694) -> (145.5528, -14.9646)
  line L559 (145.5528, -14.9646) -> (145.4575, -15.0598)
  line L560 (145.4575, -15.0598) -> (145.3623, -14.9646)
  line L561 (145.3623, -14.9646) -> (145.4575, -14.8694)
  line L562 (145.4575, -14.8694) -> (145.4575, -15.0598)
  line L563 (146.6956, -13.917) -> (146.5051, -13.8217)
  line L564 (146.5051, -13.8217) -> (146.4099, -13.7265)
  line L565 (146.4099, -13.7265) -> (146.3147, -13.536)
  line L566 (146.3147, -13.536) -> (146.3147, -13.4408)
  line L567 (146.3147, -13.4408) -> (146.4099, -13.2503)
  line L568 (146.4099, -13.2503) -> (146.5051, -13.1551)
  line L569 (146.5051, -13.1551) -> (146.6956, -13.0598)
  line L570 (146.6956, -13.0598) -> (147.0766, -13.0598)
  line L571 (147.0766, -13.0598) -> (147.2671, -13.1551)
  line L572 (147.2671, -13.1551) -> (147.3623, -13.2503)
  line L573 (147.3623, -13.2503) -> (147.4575, -13.4408)
  line L574 (147.4575, -13.4408) -> (147.4575, -13.536)
  line L575 (147.4575, -13.536) -> (147.3623, -13.7265)
  line L576 (147.3623, -13.7265) -> (147.2671, -13.8217)
  line L577 (147.2671, -13.8217) -> (147.0766, -13.917)
  line L578 (147.0766, -13.917) -> (146.6956, -13.917)
  line L579 (146.6956, -13.917) -> (146.5051, -14.0122)
  line L580 (146.5051, -14.0122) -> (146.4099, -14.1075)
  line L581 (146.4099, -14.1075) -> (146.3147, -14.2979)
  line L582 (146.3147, -14.2979) -> (146.3147, -14.6789)
  line L583 (146.3147, -14.6789) -> (146.4099, -14.8694)
  line L584 (146.4099, -14.8694) -> (146.5051, -14.9646)
  line L585 (146.5051, -14.9646) -> (146.6956, -15.0598)
  line L586 (146.6956, -15.0598) -> (147.0766, -15.0598)
  line L587 (147.0766, -15.0598) -> (147.2671, -14.9646)
  line L588 (147.2671, -14.9646) -> (147.3623, -14.8694)
  line L589 (147.3623, -14.8694) -> (147.4575, -14.6789)
  line L590 (147.4575, -14.6789) -> (147.4575, -14.2979)
  line L591 (147.4575, -14.2979) -> (147.3623, -14.1075)
  line L592 (147.3623, -14.1075) -> (147.2671, -14.0122)
  line L593 (147.2671, -14.0122) -> (147.0766, -13.917)
  line L594 (148.6956, -13.0598) -> (148.8861, -13.0598)
  line L595 (148.8861, -13.0598) -> (149.0766, -13.1551)
  line L596 (149.0766, -13.1551) -> (149.1718, -13.2503)
  line L597 (149.1718, -13.2503) -> (149.2671, -13.4408)
  line L598 (149.2671, -13.4408) -> (149.3623, -13.8217)
  line L599 (149.3623, -13.8217) -> (149.3623, -14.2979)
  line L600 (149.3623, -14.2979) -> (149.2671, -14.6789)
  line L601 (149.2671, -14.6789) -> (149.1718, -14.8694)
  line L602 (149.1718, -14.8694) -> (149.0766, -14.9646)
  line L603 (149.0766, -14.9646) -> (148.8861, -15.0598)
  line L604 (148.8861, -15.0598) -> (148.6956, -15.0598)
  line L605 (148.6956, -15.0598) -> (148.5051, -14.9646)
  line L606 (148.5051, -14.9646) -> (148.4099, -14.8694)
  line L607 (148.4099, -14.8694) -> (148.3147, -14.6789)
  line L608 (148.3147, -14.6789) -> (148.2194, -14.2979)
  line L609 (148.2194, -14.2979) -> (148.2194, -13.8217)
  line L610 (148.2194, -13.8217) -> (148.3147, -13.4408)
  line L611 (148.3147, -13.4408) -> (148.4099, -13.2503)
  line L612 (148.4099, -13.2503) -> (148.5051, -13.1551)
  line L613 (148.5051, -13.1551) -> (148.6956, -13.0598)
  line L614 (150.6004, -13.0598) -> (150.7909, -13.0598)
  line L615 (150.7909, -13.0598) -> (150.9813, -13.1551)
  line L616 (150.9813, -13.1551) -> (151.0766, -13.2503)
  line L617 (151.0766, -13.2503) -> (151.1718, -13.4408)
  line L618 (151.1718, -13.4408) -> (151.2671, -13.8217)
  line L619 (151.2671, -13.8217) -> (151.2671, -14.2979)
  line L620 (151.2671, -14.2979) -> (151.1718, -14.6789)
  line L621 (151.1718, -14.6789) -> (151.0766, -14.8694)
  line L622 (151.0766, -14.8694) -> (150.9813, -14.9646)
  line L623 (150.9813, -14.9646) -> (150.7909, -15.0598)
  line L624 (150.7909, -15.0598) -> (150.6004, -15.0598)
  line L625 (150.6004, -15.0598) -> (150.4099, -14.9646)
  line L626 (150.4099, -14.9646) -> (150.3147, -14.8694)
  line L627 (150.3147, -14.8694) -> (150.2194, -14.6789)
  line L628 (150.2194, -14.6789) -> (150.1242, -14.2979)
  line L629 (150.1242, -14.2979) -> (150.1242, -13.8217)
  line L630 (150.1242, -13.8217) -> (150.2194, -13.4408)
  line L631 (150.2194, -13.4408) -> (150.3147, -13.2503)
  line L632 (150.3147, -13.2503) -> (150.4099, -13.1551)
  line L633 (150.4099, -13.1551) -> (150.6004, -13.0598)
  line L634 (152.1242, -15.0598) -> (152.1242, -13.7265)
  line L635 (152.1242, -13.917) -> (152.2194, -13.8217)
  line L636 (152.2194, -13.8217) -> (152.4099, -13.7265)
  line L637 (152.4099, -13.7265) -> (152.6956, -13.7265)
  line L638 (152.6956, -13.7265) -> (152.8861, -13.8217)
  line L639 (152.8861, -13.8217) -> (152.9813, -14.0122)
  line L640 (152.9813, -14.0122) -> (152.9813, -15.0598)
  line L641 (152.9813, -14.0122) -> (153.0766, -13.8217)
  line L642 (153.0766, -13.8217) -> (153.2671, -13.7265)
  line L643 (153.2671, -13.7265) -> (153.5528, -13.7265)
  line L644 (153.5528, -13.7265) -> (153.7432, -13.8217)
  line L645 (153.7432, -13.8217) -> (153.8385, -14.0122)
  line L646 (153.8385, -14.0122) -> (153.8385, -15.0598)
  line L647 (154.7909, -15.0598) -> (154.7909, -13.7265)
  line L648 (154.7909, -13.917) -> (154.8861, -13.8217)
  line L649 (154.8861, -13.8217) -> (155.0766, -13.7265)
  line L650 (155.0766, -13.7265) -> (155.3623, -13.7265)
  line L651 (155.3623, -13.7265) -> (155.5528, -13.8217)
  line L652 (155.5528, -13.8217) -> (155.648, -14.0122)
  line L653 (155.648, -14.0122) -> (155.648, -15.0598)
  line L654 (155.648, -14.0122) -> (155.7432, -13.8217)
  line L655 (155.7432, -13.8217) -> (155.9337, -13.7265)
  line L656 (155.9337, -13.7265) -> (156.2194, -13.7265)
  line L657 (156.2194, -13.7265) -> (156.4099, -13.8217)
  line L658 (156.4099, -13.8217) -> (156.5051, -14.0122)
  line L659 (156.5052, -14.0122) -> (156.5052, -15.0598)
  line L660 (160.4099, -12.9646) -> (158.6956, -15.536)
  line L661 (162.9813, -13.0598) -> (163.1718, -13.0598)
  line L662 (163.1718, -13.0598) -> (163.3623, -13.1551)
  line L663 (163.3623, -13.1551) -> (163.4575, -13.2503)
  line L664 (163.4575, -13.2503) -> (163.5528, -13.4408)
  line L665 (163.5528, -13.4408) -> (163.648, -13.8217)
  line L666 (163.648, -13.8217) -> (163.648, -14.2979)
  line L667 (163.648, -14.2979) -> (163.5528, -14.6789)
  line L668 (163.5528, -14.6789) -> (163.4575, -14.8694)
  line L669 (163.4575, -14.8694) -> (163.3623, -14.9646)
  line L670 (163.3623, -14.9646) -> (163.1718, -15.0598)
  line L671 (163.1718, -15.0598) -> (162.9813, -15.0598)
  line L672 (162.9813, -15.0598) -> (162.7909, -14.9646)
  line L673 (162.7909, -14.9646) -> (162.6956, -14.8694)
  line L674 (162.6956, -14.8694) -> (162.6004, -14.6789)
  line L675 (162.6004, -14.6789) -> (162.5052, -14.2979)
  line L676 (162.5052, -14.2979) -> (162.5052, -13.8217)
  line L677 (162.5052, -13.8217) -> (162.6004, -13.4408)
  line L678 (162.6004, -13.4408) -> (162.6956, -13.2503)
  line L679 (162.6956, -13.2503) -> (162.7909, -13.1551)
  line L680 (162.7909, -13.1551) -> (162.9813, -13.0598)
  line L681 (164.5052, -14.8694) -> (164.6004, -14.9646)
  line L682 (164.6004, -14.9646) -> (164.5052, -15.0598)
  line L683 (164.5052, -15.0598) -> (164.4099, -14.9646)
  line L684 (164.4099, -14.9646) -> (164.5052, -14.8694)
  line L685 (164.5052, -14.8694) -> (164.5052, -15.0598)
  line L686 (165.8385, -13.0598) -> (166.029, -13.0598)
  line L687 (166.029, -13.0598) -> (166.2194, -13.1551)
  line L688 (166.2194, -13.1551) -> (166.3147, -13.2503)
  line L689 (166.3147, -13.2503) -> (166.4099, -13.4408)
  line L690 (166.4099, -13.4408) -> (166.5052, -13.8217)
  line L691 (166.5052, -13.8217) -> (166.5052, -14.2979)
  line L692 (166.5052, -14.2979) -> (166.4099, -14.6789)
  line L693 (166.4099, -14.6789) -> (166.3147, -14.8694)
  line L694 (166.3147, -14.8694) -> (166.2194, -14.9646)
  line L695 (166.2194, -14.9646) -> (166.029, -15.0598)
  line L696 (166.029, -15.0598) -> (165.8385, -15.0598)
  line L697 (165.8385, -15.0598) -> (165.648, -14.9646)
  line L698 (165.648, -14.9646) -> (165.5528, -14.8694)
  line L699 (165.5528, -14.8694) -> (165.4575, -14.6789)
  line L700 (165.4575, -14.6789) -> (165.3623, -14.2979)
  line L701 (165.3623, -14.2979) -> (165.3623, -13.8217)
  line L702 (165.3623, -13.8217) -> (165.4575, -13.4408)
  line L703 (165.4575, -13.4408) -> (165.5528, -13.2503)
  line L704 (165.5528, -13.2503) -> (165.648, -13.1551)
  line L705 (165.648, -13.1551) -> (165.8385, -13.0598)
  line L706 (167.1718, -13.0598) -> (168.4099, -13.0598)
  line L707 (168.4099, -13.0598) -> (167.7432, -13.8217)
  line L708 (167.7432, -13.8217) -> (168.029, -13.8217)
  line L709 (168.029, -13.8217) -> (168.2194, -13.917)
  line L710 (168.2194, -13.917) -> (168.3147, -14.0122)
  line L711 (168.3147, -14.0122) -> (168.4099, -14.2027)
  line L712 (168.4099, -14.2027) -> (168.4099, -14.6789)
  line L713 (168.4099, -14.6789) -> (168.3147, -14.8694)
  line L714 (168.3147, -14.8694) -> (168.2194, -14.9646)
  line L715 (168.2194, -14.9646) -> (168.029, -15.0598)
  line L716 (168.029, -15.0598) -> (167.4575, -15.0598)
  line L717 (167.4575, -15.0598) -> (167.2671, -14.9646)
  line L718 (167.2671, -14.9646) -> (167.1718, -14.8694)
  line L719 (170.3147, -15.0598) -> (169.1718, -15.0598)
  line L720 (169.7432, -15.0598) -> (169.7432, -13.0598)
  line L721 (169.7432, -13.0598) -> (169.5528, -13.3456)
  line L722 (169.5528, -13.3456) -> (169.3623, -13.536)
  line L723 (169.3623, -13.536) -> (169.1718, -13.6313)
  line L724 (172.1242, -13.0598) -> (171.1718, -13.0598)
  line L725 (171.1718, -13.0598) -> (171.0766, -14.0122)
  line L726 (171.0766, -14.0122) -> (171.1718, -13.917)
  line L727 (171.1718, -13.917) -> (171.3623, -13.8217)
  line L728 (171.3623, -13.8217) -> (171.8385, -13.8217)
  line L729 (171.8385, -13.8217) -> (172.029, -13.917)
  line L730 (172.029, -13.917) -> (172.1242, -14.0122)
  line L731 (172.1242, -14.0122) -> (172.2194, -14.2027)
  line L732 (172.2194, -14.2027) -> (172.2194, -14.6789)
  line L733 (172.2194, -14.6789) -> (172.1242, -14.8694)
  line L734 (172.1242, -14.8694) -> (172.029, -14.9646)
  line L735 (172.029, -14.9646) -> (171.8385, -15.0598)
  line L736 (171.8385, -15.0598) -> (171.3623, -15.0598)
  line L737 (171.3623, -15.0598) -> (171.1718, -14.9646)
  line L738 (171.1718, -14.9646) -> (171.0766, -14.8694)
  line L739 (172.9813, -13.0598) -> (172.9813, -13.4408)
  line L740 (173.7432, -13.0598) -> (173.7432, -13.4408)
  line L741 (176.6956, -15.8217) -> (176.6004, -15.7265)
  line L742 (176.6004, -15.7265) -> (176.4099, -15.4408)
  line L743 (176.4099, -15.4408) -> (176.3147, -15.2503)
  line L744 (176.3147, -15.2503) -> (176.2194, -14.9646)
  line L745 (176.2194, -14.9646) -> (176.1242, -14.4884)
  line L746 (176.1242, -14.4884) -> (176.1242, -14.1075)
  line L747 (176.1242, -14.1075) -> (176.2194, -13.6313)
  line L748 (176.2194, -13.6313) -> (176.3147, -13.3456)
  line L749 (176.3147, -13.3456) -> (176.4099, -13.1551)
  line L750 (176.4099, -13.1551) -> (176.6004, -12.8694)
  line L751 (176.6004, -12.8694) -> (176.6956, -12.7741)
  line L752 (177.2671, -13.0598) -> (178.6004, -13.0598)
  line L753 (178.6004, -13.0598) -> (177.7432, -15.0598)
  line L754 (179.2671, -13.2503) -> (179.3623, -13.1551)
  line L755 (179.3623, -13.1551) -> (179.5528, -13.0598)
  line L756 (179.5528, -13.0598) -> (180.029, -13.0598)
  line L757 (180.029, -13.0598) -> (180.2194, -13.1551)
  line L758 (180.2194, -13.1551) -> (180.3147, -13.2503)
  line L759 (180.3147, -13.2503) -> (180.4099, -13.4408)
  line L760 (180.4099, -13.4408) -> (180.4099, -13.6313)
  line L761 (180.4099, -13.6313) -> (180.3147, -13.917)
  line L762 (180.3147, -13.917) -> (179.1718, -15.0598)
  line L763 (179.1718, -15.0598) -> (180.4099, -15.0598)
  line L764 (182.7909, -15.0598) -> (182.7909, -13.0598)
  line L765 (183.648, -15.0598) -> (183.648, -14.0122)
  line L766 (183.648, -14.0122) -> (183.5528, -13.8217)
  line L767 (183.5528, -13.8217) -> (183.3623, -13.7265)
  line L768 (183.3623, -13.7265) -> (183.0766, -13.7265)
  line L769 (183.0766, -13.7265) -> (182.8861, -13.8217)
  line L770 (182.8861, -13.8217) -> (182.7909, -13.917)
  line L771 (184.8861, -15.0598) -> (184.6956, -14.9646)
  line L772 (184.6956, -14.9646) -> (184.6004, -14.8694)
  line L773 (184.6004, -14.8694) -> (184.5052, -14.6789)
  line L774 (184.5052, -14.6789) -> (184.5052, -14.1075)
  line L775 (184.5052, -14.1075) -> (184.6004, -13.917)
  line L776 (184.6004, -13.917) -> (184.6956, -13.8217)
  line L777 (184.6956, -13.8217) -> (184.8861, -13.7265)
  line L778 (184.8861, -13.7265) -> (185.1718, -13.7265)
  line L779 (185.1718, -13.7265) -> (185.3623, -13.8217)
  line L780 (185.3623, -13.8217) -> (185.4575, -13.917)
  line L781 (185.4575, -13.917) -> (185.5528, -14.1075)
  line L782 (185.5528, -14.1075) -> (185.5528, -14.6789)
  line L783 (185.5528, -14.6789) -> (185.4575, -14.8694)
  line L784 (185.4575, -14.8694) -> (185.3623, -14.9646)
  line L785 (185.3623, -14.9646) -> (185.1718, -15.0598)
  line L786 (185.1718, -15.0598) -> (184.8861, -15.0598)
  line L787 (186.6956, -15.0598) -> (186.5052, -14.9646)
  line L788 (186.5052, -14.9646) -> (186.4099, -14.7741)
  line L789 (186.4099, -14.7741) -> (186.4099, -13.0598)
  line L790 (188.2194, -14.9646) -> (188.029, -15.0598)
  line L791 (188.029, -15.0598) -> (187.648, -15.0598)
  line L792 (187.648, -15.0598) -> (187.4575, -14.9646)
  line L793 (187.4575, -14.9646) -> (187.3623, -14.7741)
  line L794 (187.3623, -14.7741) -> (187.3623, -14.0122)
  line L795 (187.3623, -14.0122) -> (187.4575, -13.8217)
  line L796 (187.4575, -13.8217) -> (187.648, -13.7265)
  line L797 (187.648, -13.7265) -> (188.029, -13.7265)
  line L798 (188.029, -13.7265) -> (188.2194, -13.8217)
  line L799 (188.2194, -13.8217) -> (188.3147, -14.0122)
  line L800 (188.3147, -14.0122) -> (188.3147, -14.2027)
  line L801 (188.3147, -14.2027) -> (187.3623, -14.3932)
  line L802 (189.0766, -14.9646) -> (189.2671, -15.0598)
  line L803 (189.2671, -15.0598) -> (189.648, -15.0598)
  line L804 (189.648, -15.0598) -> (189.8385, -14.9646)
  line L805 (189.8385, -14.9646) -> (189.9337, -14.7741)
  line L806 (189.9337, -14.7741) -> (189.9337, -14.6789)
  line L807 (189.9337, -14.6789) -> (189.8385, -14.4884)
  line L808 (189.8385, -14.4884) -> (189.648, -14.3932)
  line L809 (189.648, -14.3932) -> (189.3623, -14.3932)
  line L810 (189.3623, -14.3932) -> (189.1718, -14.2979)
  line L811 (189.1718, -14.2979) -> (189.0766, -14.1075)
  line L812 (189.0766, -14.1075) -> (189.0766, -14.0122)
  line L813 (189.0766, -14.0122) -> (189.1718, -13.8217)
  line L814 (189.1718, -13.8217) -> (189.3623, -13.7265)
  line L815 (189.3623, -13.7265) -> (189.648, -13.7265)
  line L816 (189.648, -13.7265) -> (189.8385, -13.8217)
  line L817 (190.6004, -15.8217) -> (190.6956, -15.7265)
  line L818 (190.6956, -15.7265) -> (190.8861, -15.4408)
  line L819 (190.8861, -15.4408) -> (190.9813, -15.2503)
  line L820 (190.9813, -15.2503) -> (191.0766, -14.9646)
  line L821 (191.0766, -14.9646) -> (191.1718, -14.4884)
  line L822 (191.1718, -14.4884) -> (191.1718, -14.1075)
  line L823 (191.1718, -14.1075) -> (191.0766, -13.6313)
  line L824 (191.0766, -13.6313) -> (190.9813, -13.3456)
  line L825 (190.9813, -13.3456) -> (190.8861, -13.1551)
  line L826 (190.8861, -13.1551) -> (190.6956, -12.8694)
  line L827 (190.6956, -12.8694) -> (190.6004, -12.7741)